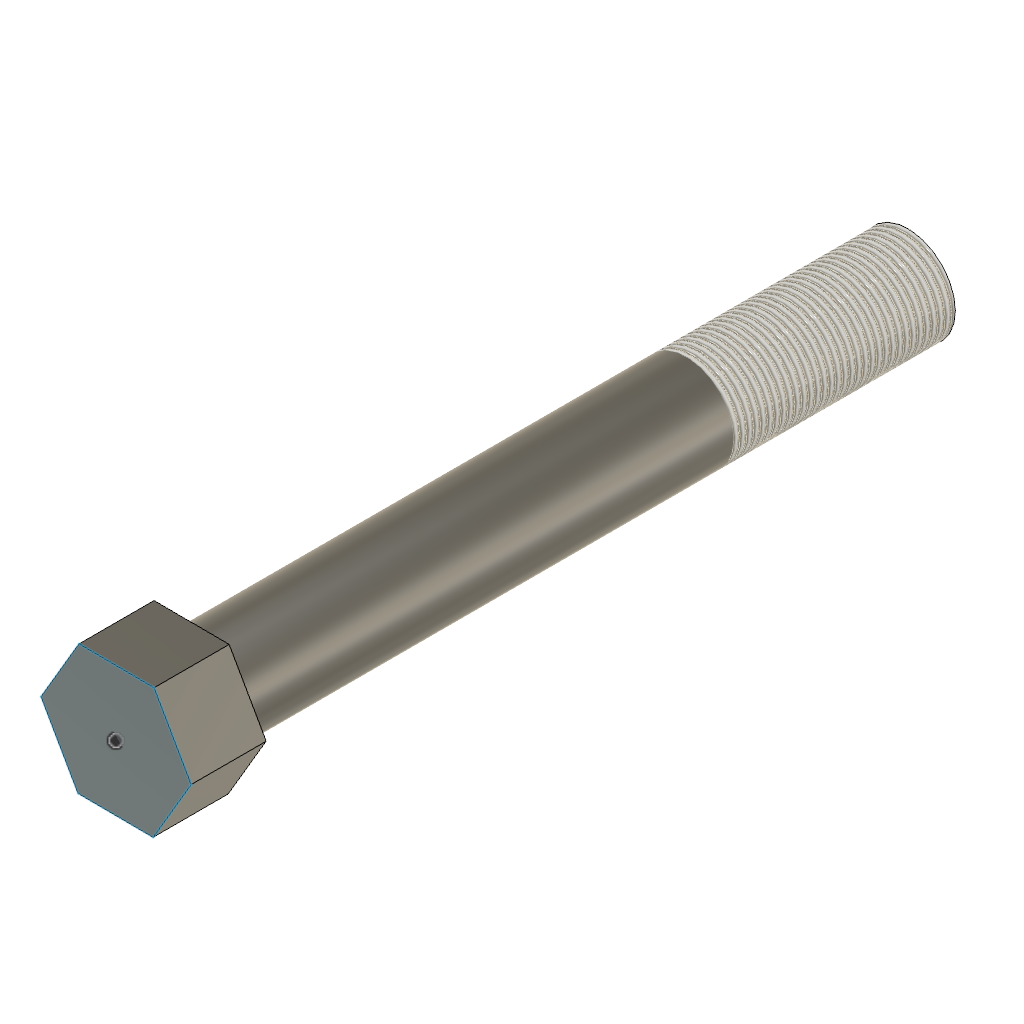
bolt (Autodesk Fusion 360 design; units mm, degrees)
part number: 2026-10-08-14-24-53-336
Autodesk Fusion 360 part; units mm, degrees
sketch "Sketch1" plane through (0, 0, 0) normal (0, 1, 0) x (1, 0, 0)
  line L0 (21.9994, 0.1571) -> (10.8636, 19.1306)
  line L1 (10.8636, 19.1306) -> (-11.1358, 18.9735)
  line L2 (-11.1358, 18.9735) -> (-21.9994, -0.1571)
  line L3 (-21.9994, -0.1571) -> (-10.8636, -19.1306)
  line L4 (-10.8636, -19.1306) -> (11.1358, -18.9735)
  line L5 (11.1358, -18.9735) -> (21.9994, 0.1571)
  dimension "d1" = 22
  measures "d1" distance of L0.start origin
extrude "Extrude1" add sketch "Sketch1" along normal blind 22
sketch "Sketch3" plane through (0, 22, 0) normal (0, 1, 0) x (-1, 0, 0)
  line L0 (-11.1358, 18.9735) -> (-21.9994, -0.1571)
  line L1 (-21.9994, -0.1571) -> (-10.8636, -19.1306)
  line L2 (-10.8636, -19.1306) -> (11.1358, -18.9735)
  line L3 (11.1358, -18.9735) -> (21.9994, 0.1571)
  line L4 (21.9994, 0.1571) -> (10.8636, 19.1306)
  line L5 (10.8636, 19.1306) -> (-11.1358, 18.9735)
  circle A0 centre (0, 0) radius 14
  dimension "d11" = 28
  constraint coincident A0.centre origin
  measures "d11" diameter of A0
extrude "Extrude4" add sketch "Sketch3" along normal blind 210 contours A0
thread "Thread2" "ISO Metric profile 28.0 M28x2 M28x2 6g" major diameter 27.822 minor diameter 25.5289 pitch 2 angle 60 resizes the face on face at (-13.9304, 162, -1.3939) from (0, 167, 0) to (0, 232, 0)
